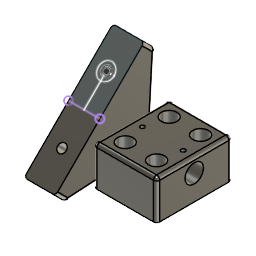
DiyBeltTensioner2040Holder (Autodesk Fusion 360 design; units mm, degrees)
part number: 2026-10-20-05-39-49-588
Autodesk Fusion 360 part; units mm, degrees
sketch "Sketch1" plane through (0, 0, 0) normal (0, 0, 1) x (1, 0, 0)
  circle A0 centre (-32.6464, -1.532) radius 2.75
  circle A1 centre (-12.6464, -1.532) radius 2.75
  circle A2 centre (-32.6464, 26.468) radius 2.75
  circle A3 centre (-12.6464, 26.468) radius 2.75
  line L0 (-32.6464, 26.468) -> (-12.6464, 26.468)
  line L1 (-12.6464, 26.468) -> (-12.6464, -1.532)
  line L2 (-12.6464, -1.532) -> (-32.6464, -1.532)
  line L3 (-32.6464, -1.532) -> (-32.6464, 26.468)
  circle A4 centre (-32.6464, 26.468) radius 5
  circle A5 centre (-12.6464, 26.468) radius 5
  circle A6 centre (-12.6464, -1.532) radius 5
  circle A7 centre (-32.6464, -1.532) radius 5
  line L4 (-12.6464, -1.532) -> (-32.6464, 26.468) construction
  line L5 (-32.6464, -1.532) -> (-12.6464, 26.468) construction
  line L6 (30.2672, 18.468) -> (-75.5599, 18.468)
  line L7 (-75.5599, 18.468) -> (-75.5599, 6.468)
  line L8 (-75.5599, 6.468) -> (30.2672, 6.468)
  line L9 (30.2672, 6.468) -> (30.2672, 18.468)
  line L10 (30.2672, 18.468) -> (-75.5599, 6.468) construction
  line L11 (-75.5599, 18.468) -> (30.2672, 6.468) construction
  line L12 (-12.6464, 3.468) -> (1.9201, 3.468) construction
  line L13 (-2.6464, 36.468) -> (-42.6464, 36.468)
  line L14 (-42.6464, 36.468) -> (-42.6464, -11.532)
  line L15 (-42.6464, -11.532) -> (-2.6464, -11.532)
  line L16 (-2.6464, -11.532) -> (-2.6464, 36.468)
  line L17 (-2.6464, 36.468) -> (-42.6464, -11.532) construction
  line L18 (-42.6464, 36.468) -> (-2.6464, -11.532) construction
  line L19 (-12.6464, 31.468) -> (14.4079, 31.468) construction
  line L20 (-42.6464, 12.468) -> (-2.6464, 12.468)
  point P0 (-22.6464, 12.468)
  point P1 (-22.6464, 12.468)
  dimension "d1" = 5.5
  dimension "d2" = 10
  dimension "d3" = 20
  dimension "d4" = 12
  dimension "d5" = 3
  dimension "d6" = 40
  dimension "d7" = 5
  constraint horizontal L0
  constraint vertical L1
  constraint horizontal L2
  constraint vertical L3
  constraint coincident A1.centre L1.end
  constraint coincident A2.centre L0.start
  constraint coincident A3.centre L0.end
  constraint coincident A0.centre L2.end
  constraint equal A2 A3
  constraint equal A1 A3
  constraint equal A0 A1
  constraint concentric A2 A4
  constraint concentric A3 A5
  constraint concentric A1 A6
  constraint equal A4 A7
  constraint equal A4 A5
  constraint equal A5 A6
  constraint horizontal L6
  constraint perpendicular L6 L7
  constraint parallel L6 L8
  constraint parallel L7 L9
  constraint coincident L10 P1
  constraint coincident L11 P1
  constraint midpoint L4 P1
  constraint coincident L1 L12.start
  constraint coincident A6 L12.start
  constraint tangent A6 L12
  constraint horizontal L13
  constraint perpendicular L13 L14
  constraint parallel L13 L15
  constraint parallel L14 L16
  constraint coincident L17 P1
  constraint coincident L18 P1
  constraint coincident P1 P0
  constraint coincident A5 L19.start
  constraint tangent A5 L19
  constraint perpendicular L1 L19
  constraint perpendicular L16 L20
  constraint coincident L16 L20.end
  constraint coincident L14 L20.start
  measures "d1" diameter of A2
  measures "d2" diameter of A4
  measures "d3" distance of A1.centre A0.centre
  measures "d4" distance of L6.start L8.end
  measures "d5" distance of L8 L12
  measures "d6" distance of L14 L16
  measures "d7" distance of L13 L19
extrude "Extrude1" add sketch "Sketch1" along normal blind 15 contours L3 L6 L14 L20 | L1 L3 L6 L20 | L0 L1 L3 A4 A5 L6 L13 L14 L16 | L0 L1 L3 A4 A5 L6 | L1 L6 L16 L20 | A2 L0 L3 A4 | A2 L0 L3 A4 | A3 L0 L1 A5 | A3 L0 L1 A5 makes body 1
extrude "Extrude2" add sketch "Sketch1" along normal blind 10 from surface at 15 contours L3 L6 L14 L20 | L1 L3 L6 L20 | L0 L1 L3 A4 A5 L6 L13 L14 L16 | L0 L1 L3 A4 A5 L6 | L1 L6 L16 L20 bodies 1
sketch "Sketch2" plane through (-42.6464, 0, 0) normal (-1, 0, 0) x (0, -1, 0)
  line L0 (-36.468, 0) -> (-12.468, 0)
  line L1 (-12.468, 0) -> (-12.468, 25)
  line L2 (-12.468, 25) -> (-36.468, 25)
  line L3 (-36.468, 25) -> (-36.468, 0)
  circle A0 centre (-12.468, 15.85) radius 5.85
  line L4 (-12.468, 10) -> (-3.5302, 10)
  line L5 (-36.468, 0) -> (11.532, 0)
  dimension "d13" = 11.7
  dimension "d14" = 10
  constraint coincident L1 A0.centre
  constraint coincident L1 L4.start
  constraint coincident A0 L4.start
  constraint tangent A0 L4
  measures "d13" diameter of A0
  measures "d14" distance of L4 L5
extrude "Extrude3" cut sketch "Sketch2" against normal up to surface (40 mm away) contours L1 A0 picked at (-15.091, 17.4046) bodies 1
fillet "Fillet1" radius 2 5 edges at (-42.6464, 36.468, 12.5) (-2.6464, 36.468, 12.5) (-22.6464, 36.468, 25) (-2.6464, 24.468, 25) (-42.6464, 24.468, 25) on bodies 1
sketch "Sketch3" plane through (0, 0, 25) normal (0, 0, 1) x (-1, 0, 0)
  line L0 (40.6464, -34.468) -> (40.6464, -12.468)
  line L1 (40.6464, -12.468) -> (4.6464, -12.468)
  line L2 (4.6464, -12.468) -> (4.6464, -34.468)
  line L3 (4.6464, -34.468) -> (40.6464, -34.468)
  circle A0 centre (32.6464, -26.468) radius 5
  circle A1 centre (12.6464, -26.468) radius 5
  circle A2 centre (35.6464, -12.468) radius 1.35
  circle A3 centre (9.6464, -12.468) radius 1.35
  dimension "d19" = 5
  dimension "d20" = 5
  dimension "d21" = 2.7
  constraint coincident L1 A2.centre
  constraint coincident L1 A3.centre
  constraint equal A2 A3
  measures "d19" distance of L0.end A2.centre
  measures "d20" distance of L1.end A3.centre
  measures "d21" diameter of A2
extrude "Extrude4" cut sketch "Sketch3" along normal up to surface contours L1 A2 | L1 A3 picked at (35.4609, -13.12) picked at (9.5512, -12.9738) end surface at (-15.9797, 14.761, 21.2319) on bodies 1 bodies 1
mirror "Mirror1" about plane through (-42.6464, 12.468, 0) normal (0, -1, 0) of bodies 1 merged
ref_plane "WorkPlane1" through (-43.6464, 12.468, 11.5) normal (-1, 0, 0) x (0, -1, 0)
sketch "Sketch4" plane through (-43.6464, 0, 0) normal (-1, 0, 0) x (0, -1, 0)
  circle A0 centre (-12.468, 15.85) radius 5.85
  line L0 (-34.468, 25) -> (9.532, 25)
  line L1 (20.7847, 20.8184) -> (-7.4996, 49.1027)
  line L2 (-12.468, 15.85) -> (6.6426, 34.9605)
  line L3 (-12.468, 15.85) -> (-12.468, 44.2151) construction
  circle A1 centre (-12.468, 15.85) radius 13.85
  line L4 (-7.4996, 49.1027) -> (-21.6417, 63.2448)
  line L5 (-21.6417, 63.2448) -> (-28.7128, 56.1737)
  line L6 (-28.7128, 56.1737) -> (-26.2941, 15.0371)
  line L7 (-12.468, 2) -> (-28.0815, 2)
  line L8 (-12.468, 15.85) -> (-22.2614, 6.0566)
  line L9 (-16.6045, 11.7134) -> (-42.6181, 33.7557)
  point P0 (-34.468, 0)
  dimension "d28" = 40
  dimension "d29" = 45
  dimension "d30" = 5
  dimension "d31" = 40
  dimension "d32" = 10
  dimension "d33" = 2
  constraint coincident A0.centre L2.start
  constraint midpoint L1 L2.end
  constraint perpendicular L1 L2
  constraint vertical L3
  constraint concentric A0 A1
  constraint parallel L1 L4
  constraint perpendicular L4 L5
  constraint coincident A1 L6.end
  constraint tangent A1 L6
  constraint coincident A1 L7.start
  constraint horizontal L7
  constraint tangent A1 L7
  constraint coincident A1 L8.end
  constraint parallel L2 L8
  constraint coincident A0 L9.start
  constraint coincident L8 L9.start
  measures "d28" distance of L1.start L1.end
  measures "d29" angle of L2 L3
  measures "d30" distance of L0.end L1
  measures "d31" distance of L2.end L4.end
  measures "d32" distance of L4.end L5.end
  measures "d33" distance of L7 P0
extrude "Extrude5" add sketch "Sketch4" along normal blind 20 separate body contours A0 L0 L2 A1 L9 | A1 L8 L9 | L0 A1 L6 L9 | A1 L6 L9 | L0 L2 A1 | L0 L1 L2 A1 L4 L5 L6 picked at (-15.8597, 25.4795) makes body 2
sketch "Sketch5" plane through (0, -20.8015, 20.8015) normal (0, -0.707107, 0.707107) x (1, 0, 0)
  line L0 (-43.6464, 20.0238) -> (-43.6464, 60.0238)
  line L1 (-43.6464, 60.0238) -> (-63.6464, 60.0238)
  line L2 (-63.6464, 60.0238) -> (-63.6464, 20.0238)
  line L3 (-63.6464, 20.0238) -> (-43.6464, 20.0238)
  circle A0 centre (-53.6464, 40.0238) radius 2.75
  circle A1 centre (-53.6464, 40.0238) radius 5
  line L4 (-43.6464, 20.0238) -> (-63.6464, 20.0238)
  line L5 (-53.6464, 20.0238) -> (-53.6464, 40.0238)
  dimension "d36" = 5.5
  dimension "d37" = 10
  dimension "d38" = 20
  constraint concentric A0 A1
  constraint midpoint L4 L5.start
  constraint coincident A0.centre A1.centre
  constraint vertical L5
  measures "d36" diameter of A0
  measures "d37" diameter of A1
  measures "d38" distance of L5.start A0.centre
extrude "Extrude6" cut sketch "Sketch5" against normal blind 67 contours A0 bodies 2
extrude "Extrude7" cut sketch "Sketch5" along normal up to surface from surface at -15 contours A1 end surface through (-43.6464, 28.7128, 56.1737) normal (0, 0.998276, -0.058695) offset 0 bodies 2
fillet "Fillet2" radius 2 7 edges at (-63.6464, 25.1772, 59.7093) (-43.6464, 25.1772, 59.7093) (-53.6464, 28.7128, 56.1737) (-63.6464, 27.5034, 35.6054) (-63.6464, 25.1026, 10.1764) (-43.6464, 27.5034, 35.6054) (-43.6464, 25.1026, 10.1764) on bodies 2
mirror "Mirror2" about plane through (-43.6464, 8.3314, 19.9866) normal (0, -0.707107, -0.707107) of bodies 2 merged
equation "d20 = d19"
named bodies: "BeltTensionerAdapter", "RigAdapter"
